Autodesk Fusion 360 part; units mm, degrees
(part 2 of 3)
sketch "Sketch7" plane through (0, 0, 0) normal (-1, 0, 0) x (0, -1, 0)
  line L0 (65.405, -4.7625) -> (65.405, -1.5875)
  line L1 (65.405, -1.5875) -> (133.35, -1.5875)
  line L2 (133.35, -1.5875) -> (133.35, 4.7625)
  line L3 (133.35, 4.7625) -> (-31.75, 4.7625)
  line L4 (-31.75, 4.7625) -> (-31.75, -4.7625)
  line L5 (-31.75, -4.7625) -> (65.405, -4.7625)
  circle A0 centre (117.475, 1.5875) radius 2.1
  dimension "d33" = 4.2
  dimension "d34" = 3.175
  dimension "d35" = 15.875
  measures "d33" diameter of A0
  measures "d34" distance of L3 A0.centre
  measures "d35" distance of L2 A0.centre
extrude "Extrude6" cut sketch "Sketch7" against normal blind 6.35 contours A0
sketch "Sketch8" plane through (0, 0, 0) normal (-1, 0, 0) x (0, -1, 0)
  circle A0 centre (117.475, 1.5875) radius 2.1
  line L0 (65.405, -4.7625) -> (65.405, -1.5875)
  line L1 (65.405, -1.5875) -> (133.35, -1.5875)
  line L2 (133.35, -1.5875) -> (133.35, 4.7625)
  line L3 (133.35, 4.7625) -> (-31.75, 4.7625)
  line L4 (-31.75, 4.7625) -> (-31.75, -4.7625)
  line L5 (-31.75, -4.7625) -> (65.405, -4.7625)
  circle A1 centre (117.475, 11.4427) radius 2.1
  circle A2 centre (117.475, 11.4427) radius 3.175
  circle A3 centre (106.045, 11.4427) radius 2.1
  circle A4 centre (106.045, 11.4427) radius 3.175
  line L6 (117.475, 8.2677) -> (106.045, 8.2677)
  line L7 (117.475, 14.6177) -> (106.045, 14.6177)
  line L8 (106.045, 14.6177) -> (70.9402, 14.6177)
  line L9 (70.9402, 14.6177) -> (65.405, 6.5046)
  line L10 (106.045, 8.2677) -> (74.295, 8.2677)
  line L11 (74.295, 8.2677) -> (65.405, -4.7625)
  line L12 (65.405, 6.5046) -> (65.405, -4.7625)
  line L13 (65.405, 6.5046) -> (64.2164, 4.7625)
  line L14 (120.65, 8.2677) -> (102.87, 8.2677)
  line L15 (102.87, 8.2677) -> (102.87, 14.6177)
  line L16 (102.87, 14.6177) -> (120.65, 14.6177)
  line L17 (120.65, 14.6177) -> (120.65, 8.2677)
  dimension "d38" = 4.2
  dimension "d39" = 9.8552
  dimension "d40" = 6.35
  dimension "d45" = 4.2
  dimension "d46" = 6.35
  dimension "d47" = 11.43
  dimension "d66" = 6.35
  dimension "d68" = 31.75
  dimension "d69" = 6.35
  constraint vertical A0.centre A1.centre
  constraint concentric A1 A2
  constraint concentric A3 A4
  constraint horizontal A1.centre A3.centre
  constraint coincident A2 L6.start
  constraint coincident A4 L6.end
  constraint coincident A2 L7.start
  constraint coincident A4 L7.end
  constraint tangent A4 L7
  constraint horizontal L6
  constraint horizontal L7
  constraint parallel L7 L8
  constraint parallel L3 L10
  constraint coincident L0.start L5.end
  constraint parallel L9 L11
  constraint vertical L9.end L0.start
  constraint coincident L3 L13.end
  constraint parallel L9 L13
  constraint horizontal L14
  constraint vertical L15
  constraint horizontal L16
  constraint vertical L17
  constraint coincident L8 L15.end
  constraint coincident L10 L14.end
  constraint tangent A2 L17
  constraint tangent A4 L15
  measures "d38" diameter of A1
  measures "d39" vertical distance of A0.centre A1.centre
  measures "d40" diameter of A2
  measures "d45" diameter of A3
  measures "d46" diameter of A4
  measures "d47" distance of A1.centre A3.centre
  measures "d66" distance of L8 L10
  measures "d68" distance of L6.end L10.end
  measures "d69" distance of L9 L11
extrude "Extrude7" cut sketch "Sketch8" against normal blind 6.35 contours L0 L1 L11 L12 | L1 L2 L3 L11
extrude "Extrude8" add sketch "Sketch8" along normal blind -6.35 and the other way blind 2.54 contours L0 L1 L11 L12 | L1 L3 L11 L12 | L3 L8 L9 L10 L11 L12 L15 | L3 L12 L13 | A4 L10 L14 L15 | A4 L8 L15 L16 | A4 | A2 A4 L6 L7 L14 L16 | A2 | A2 L14 L17 | A2 L16 L17 | A1 | A3
extrude "Extrude9" add sketch "Sketch8" against normal blind 2.54 contours L0 L1 L11 L12 | A4 L10 L14 L15 | A4 L8 L15 L16 | A4 | A2 A4 L6 L7 L14 L16 | A2 | A2 L14 L17 | A2 L16 L17 | A1 | A3
sketch "Sketch10" plane through (0, 0, -4.7625) normal (0, 0, -1) x (1, 0, 0)
  line L0 (6.35, 65.405) -> (0, 65.405)
  line L1 (0, 65.405) -> (0, -31.75)
  line L2 (0, -31.75) -> (6.35, -31.75)
  line L3 (6.35, -31.75) -> (6.35, 65.405)
  line L4 (6.35, -31.75) -> (0, -31.75)
  line L5 (0, -31.75) -> (0, 65.405)
  line L6 (0, 65.405) -> (6.35, 65.405)
  line L7 (6.35, 65.405) -> (6.35, -31.75)
  constraint horizontal L4
  constraint vertical L5
  constraint horizontal L6
  constraint vertical L7
  constraint coincident L0.end L1.start
  constraint coincident L2.end L3.start
extrude "Extrude12" add sketch "Sketch10" along normal blind 0.4318
sketch "Sketch11" plane through (0, 31.75, 0) normal (0, 1, 0) x (-1, 0, 0)
  line L0 (0, -5.1943) -> (0, 4.7625)
  line L1 (0, 4.7625) -> (-6.35, 4.7625)
  line L2 (-6.35, 4.7625) -> (-6.35, -5.1943)
  line L3 (-6.35, -5.1943) -> (0, -5.1943)
  line L4 (0, -5.1943) -> (-6.35, -5.1943)
  line L5 (-6.35, -5.1943) -> (-6.35, 4.7625)
  line L6 (-6.35, 4.7625) -> (0, 4.7625)
  line L7 (0, 4.7625) -> (0, -5.1943)
  constraint horizontal L4
  constraint vertical L5
  constraint horizontal L6
  constraint vertical L7
  constraint coincident L1.end L2.start
  constraint coincident L0.start L3.end
extrude "Extrude13" add sketch "Sketch11" along normal blind 12.7
sketch "Sketch12" plane through (0, 0, 4.7625) normal (0, 0, 1) x (-1, 0, 0)
  line L0 (-2.54, 64.2164) -> (-6.35, 64.2164)
  line L1 (-6.35, 64.2164) -> (-6.35, -44.45)
  line L2 (-6.35, -44.45) -> (0, -44.45)
  line L3 (0, -44.45) -> (0, 71.9035)
  line L4 (0, 71.9035) -> (-2.54, 71.9035)
  line L5 (-2.54, 71.9035) -> (-2.54, 64.2164)
  line L6 (0, -44.45) -> (-6.35, -44.45)
  line L7 (-6.35, -44.45) -> (-6.35, 6.35)
  line L8 (-6.35, 6.35) -> (0, 6.35)
  line L9 (0, 6.35) -> (0, -44.45)
  dimension "d74" = 50.8
  constraint horizontal L6
  constraint vertical L7
  constraint horizontal L8
  constraint vertical L9
  constraint coincident L1 L7.end
  constraint coincident L2.end L3.start
  measures "d74" distance of L2.end L8.end
extrude "Extrude14" add sketch "Sketch12" along normal blind 6.35 contours L1 L2 L3 L6 L7 L8 L9
sketch "Sketch13" plane through (6.35, 0, 0) normal (1, 0, 0) x (0, 1, 0)
  line L0 (-6.35, 4.7625) -> (-64.2164, 4.7625)
  line L1 (-64.2164, 4.7625) -> (-70.9402, 14.6177)
  line L2 (-70.9402, 14.6177) -> (-120.65, 14.6177)
  line L3 (-120.65, 14.6177) -> (-120.65, 8.2677)
  line L4 (-120.65, 8.2677) -> (-74.295, 8.2677)
  line L5 (-74.295, 8.2677) -> (-65.405, -4.7625)
  line L6 (-65.405, -4.7625) -> (-65.405, -5.1943)
  line L7 (-65.405, -5.1943) -> (44.45, -5.1943)
  line L8 (44.45, -5.1943) -> (44.45, 11.1125)
  line L9 (44.45, 11.1125) -> (-6.35, 11.1125)
  line L10 (-6.35, 11.1125) -> (-6.35, 4.7625)
  line L11 (44.45, -5.1943) -> (-6.35, -5.1943)
  line L12 (-0.4841, 4.9657) -> (-6.35, -5.1943)
  line L13 (44.45, -5.1943) -> (44.45, 4.9657)
  line L14 (-0.4841, 4.9657) -> (44.45, 4.9657)
  dimension "d77" = 10.16
  dimension "d78" = 50.8
  dimension "d79" = 60
  constraint coincident L7.end L8.start
  constraint coincident L7 L11.end
  constraint coincident L8 L13.end
  constraint horizontal L14
  measures "d77" distance of L7.end L13.end
  measures "d78" distance of L7.end L11.end
  measures "d79" angle of L11 L12
extrude "Extrude15" cut sketch "Sketch13" against normal blind 6.35 contours L7 L8 L11 L12 L13 L14
fillet "Fillet1" radius 19.05 1 edges at (3.175, -6.35, 4.7625)
fillet "Fillet2" radius 6.35 1 edges at (3.175, -0.4841, 4.9657)
sketch "Sketch15" plane through (0, 44.45, 0) normal (0, 1, 0) x (-1, 0, 0)
  line L0 (-6.35, 4.9657) -> (0, 4.9657)
  line L1 (0, 4.9657) -> (0, 11.1125)
  line L2 (0, 11.1125) -> (-6.35, 11.1125)
  line L3 (-6.35, 11.1125) -> (-6.35, 4.9657)
  line L4 (34.925, 34) -> (-41.275, 34)
  line L5 (-41.275, 34) -> (-41.275, -42.2)
  line L6 (-41.275, -42.2) -> (34.925, -42.2)
  line L7 (34.925, -42.2) -> (34.925, 34)
  line L8 (34.925, 34) -> (-41.275, -42.2) construction
  line L9 (-41.275, 34) -> (34.925, -42.2) construction
  point P0 (-3.175, -4.1)
  dimension "d92" = 76.2
  dimension "d93" = 76.2
  dimension "d94" = 9.0657
  dimension "d95" = 34.925
  constraint horizontal L4
  constraint perpendicular L4 L5
  constraint parallel L4 L6
  constraint parallel L5 L7
  constraint coincident L8 P0
  constraint coincident L9 P0
  measures "d92" distance of L5.end L6.end
  measures "d93" distance of L4.end L5.end
  measures "d94" distance of L0 P0
  measures "d95" distance of L1 L7
extrude "Extrude19" cut sketch "Sketch15" against normal blind 118.745 contours L0 L1 L2 L3 | L4 L5 L6 L7
extrude "Extrude20" cut 1 faces at (3.81, -74.295, 10.3844) along direction (0, -1, 0) blind 12.7
extrude "Extrude16" [suppressed]
extrude "Extrude17" [suppressed]
sketch "Sketch14" plane through (6.35, 0, 0) normal (1, 0, 0) x (0, 1, 0)
  line L0 (-6.35, -5.1943) -> (-2.3172, 1.7907)
  arc A0 (3.1821, 4.9657) -> (-2.3172, 1.7907) centre (3.1821, -1.3843) ccw
  line L1 (3.1821, 4.9657) -> (44.45, 4.9657)
  line L2 (44.45, 4.9657) -> (44.45, 11.1125)
  line L3 (44.45, 11.1125) -> (-6.35, 11.1125)
  arc A1 (-20.549, 4.7625) -> (-6.35, 11.1125) centre (-20.549, 23.8125) ccw
  line L4 (-20.549, 4.7625) -> (-64.2164, 4.7625)
  line L5 (-64.2164, 4.7625) -> (-70.9402, 14.6177)
  line L6 (-70.9402, 14.6177) -> (-120.65, 14.6177)
  line L7 (-120.65, 14.6177) -> (-120.65, 8.2677)
  line L8 (-120.65, 8.2677) -> (-74.295, 8.2677)
  line L9 (-74.295, 8.2677) -> (-65.405, -4.7625)
  line L10 (-65.405, -4.7625) -> (-65.405, -5.1943)
  line L11 (-65.405, -5.1943) -> (-6.35, -5.1943)
  line L12 (-74.295, 8.2677) -> (-74.295, 14.6177)
  constraint coincident L8.end L9.start
  constraint coincident L6 L12.end
  constraint perpendicular L6 L12
extrude "Extrude18" [suppressed]
sketch "Sketch9" plane through (6.35, 0, 0) normal (1, 0, 0) x (0, 1, 0)
  line L0 (31.75, -5.1943) -> (31.75, 4.7625)
  line L1 (31.75, 4.7625) -> (-64.2164, 4.7625)
  line L2 (17.4625, -1.5875) -> (17.4625, -4.7625)
  line L3 (17.4625, -4.7625) -> (7.9375, -4.7625)
  line L4 (7.9375, -4.7625) -> (7.9375, -1.5875)
  line L5 (7.9375, -1.5875) -> (17.4625, -1.5875)
  line L6 (0, -2.1971) -> (7.9375, -2.1971)
  line L7 (-64.2164, 4.7625) -> (-70.9402, 14.6177)
  line L8 (-70.9402, 14.6177) -> (-120.65, 14.6177)
  line L9 (-120.65, 14.6177) -> (-120.65, 8.2677)
  line L10 (-120.65, 8.2677) -> (-74.295, 8.2677)
  line L11 (-74.295, 8.2677) -> (-65.405, -4.7625)
  line L12 (-65.405, -4.7625) -> (-65.405, -5.1943)
  line L13 (-65.405, -5.1943) -> (31.75, -5.1943)
  dimension "d55" = 9.525
  dimension "d56" = 3.175
  dimension "d57" = 7.9375
  constraint vertical L2
  constraint horizontal L3
  constraint vertical L4
  constraint perpendicular L2 L5
  constraint coincident L4 L6.end
  constraint perpendicular L4 L6
  measures "d55" distance of L4.end L2.start
  measures "d56" distance of L2.end L2.start
  measures "d57" distance of L6.start L6.end
extrude "Extrude10" [suppressed]
extrude "Extrude11" [suppressed]
equation "d7 = 0.5 in - ( 0.2 / 2 ) * 1 in"
equation "d10 = ( 0.375 / 2 ) * 1 in"
equation "d11 = ( ( 1.5 - 1 ) / 2 ) * 1 in"
equation "d39 = 0.263 in + 0.125 in"

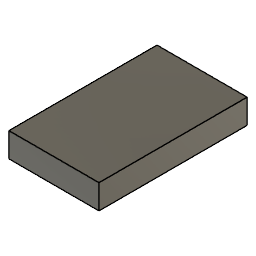
design "Biggest 5 pack ever"
Autodesk Fusion 360 part; units mm, degrees
sketch "Sketch1" plane through (0, 0, 0) normal (0, 0, 1) x (1, 0, 0)
  line L0 (0, 0) -> (58.928, 0)
  line L1 (58.928, 0) -> (58.928, 96.8502)
  line L2 (58.928, 96.8502) -> (0, 96.8502)
  line L3 (0, 96.8502) -> (0, 0)
  dimension "d1" = 96.8502
  dimension "d2" = 58.928
  constraint horizontal L0
  constraint vertical L1
  constraint horizontal L2
  constraint vertical L3
  constraint coincident L0.start L3.end
  measures "d1" distance of L0.start L2.end
  measures "d2" distance of L0.start L0.end
extrude "Extrude1" add sketch "Sketch1" along normal blind 16.002

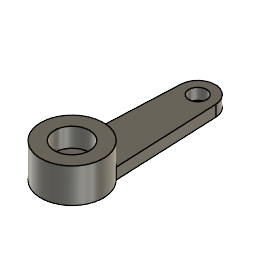
design "MicroServo horn"
Autodesk Fusion 360 part; units mm, degrees
sketch "Sketch1" plane through (0, 0, 0) normal (0, 0, 1) x (1, 0, 0)
  circle A0 centre (0, 0) radius 3.5243
  line L0 (-2.4892, 2.4948) -> (-1.9685, 14.2773)
  line L1 (2.4892, 2.4948) -> (1.9685, 14.2773)
  arc A1 (1.9685, 14.2773) -> (-1.9685, 14.2773) centre (0, 14.1903) ccw
  line L2 (-12.7, 16.1608) -> (12.7, 16.1608)
  line L3 (-12.7, -3.5242) -> (12.7, -3.5243)
  circle A2 centre (0, 14.1903) radius 1
  dimension "d1" = 7.0485
  dimension "d2" = 4.9784
  dimension "d5" = 19.685
  dimension "d7" = 3.937
  dimension "d8" = 2
  dimension "d9" = 25.4
  dimension "d10" = 12.7
  constraint coincident A0.centre origin
  constraint coincident A0 L0.start
  constraint coincident A0 L1.start
  constraint tangent L0 A1
  constraint horizontal L2
  constraint tangent A1 L2
  constraint vertical A0.centre A1.centre
  constraint horizontal L0.end L1.end
  constraint tangent A0 L3
  constraint horizontal L3
  constraint horizontal L0.start L1.start
  constraint concentric A1 A2
  constraint vertical L2.start L3.start
  constraint vertical L2.end L3.end
  measures "d1" diameter of A0
  measures "d2" horizontal distance of L0.start L1.start
  measures "d5" distance of L2 L3
  measures "d7" distance of L0.end L1.end
  measures "d8" diameter of A2
  measures "d9" distance of L2.start L2.end
  measures "d10" horizontal distance of A1.centre L2.start
extrude "Extrude1" add sketch "Sketch1" along normal blind 1.27
extrude "Extrude2" add sketch "Sketch1" along normal blind 3.8735 contours A0
sketch "Sketch2" plane through (0, 0, 3.8735) normal (0, 0, 1) x (-1, 0, 0)
  circle A0 centre (0, 0) radius 3.5242
  circle A1 centre (0, 0) radius 1.9812
  dimension "d15" = 3.9624
  constraint coincident A0.centre A1.centre
  measures "d15" diameter of A1
extrude "Extrude3" cut sketch "Sketch2" against normal blind 2.159 contours A1

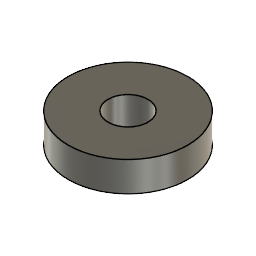
design "Front Wheel"
Autodesk Fusion 360 part; units mm, degrees
sketch "Sketch1" plane through (0, 0, 0) normal (0, 0, 1) x (1, 0, 0)
  circle A0 centre (0, 0) radius 19.05
  circle A1 centre (0, 0) radius 6.35
  dimension "d1" = 12.7
  dimension "d2" = 38.1
  constraint coincident A0.centre A1.centre
  measures "d1" diameter of A1
  measures "d2" diameter of A0
extrude "Extrude1" add sketch "Sketch1" along normal blind 9.525
equation "d3 = ( 3 / 8 ) * 1 in"

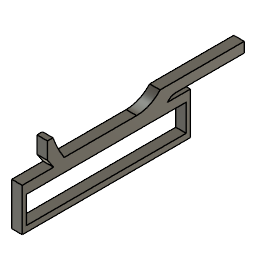
design "Left Cross Base Beam"
Autodesk Fusion 360 part; units mm, degrees
sketch "Sketch1" plane through (0, 0, 0) normal (1, 0, 0) x (0, 1, 0)
  circle A0 centre (0, 0) radius 2.1971
  circle A1 centre (25.4, 0) radius 2.1971
  line L0 (10.16, 2.54) -> (15.24, 2.54)
  line L1 (15.24, 2.54) -> (15.24, -2.54)
  line L2 (15.24, -2.54) -> (10.16, -2.54)
  line L3 (10.16, -2.54) -> (10.16, 2.54)
  line L4 (-6.35, 4.7625) -> (31.75, 4.7625)
  line L5 (31.75, 4.7625) -> (31.75, -4.7625)
  line L6 (31.75, -4.7625) -> (-6.35, -4.7625)
  line L7 (-6.35, -4.7625) -> (-6.35, 4.7625)
  dimension "d1" = 25.4
  dimension "d2" = 4.3942
  dimension "d3" = 4.3942
  dimension "d4" = 5.08
  dimension "d5" = 5.08
  dimension "d6" = 2.54
  dimension "d7" = 10.16
  dimension "d8" = 9.525
  dimension "d9" = 38.1
  dimension "d10" = 4.7625
  dimension "d11" = 6.35
  constraint horizontal A0.centre A1.centre
  constraint horizontal L0
  constraint vertical L1
  constraint horizontal L2
  constraint vertical L3
  constraint coincident A0.centre origin
  constraint horizontal L4
  constraint vertical L5
  constraint horizontal L6
  constraint vertical L7
  measures "d1" distance of A0.centre A1.centre
  measures "d2" diameter of A0
  measures "d3" diameter of A1
  measures "d4" distance of L0.start L0.end
  measures "d5" distance of L0.start L2.end
  measures "d6" distance of A0.centre L0
  measures "d7" horizontal distance of A0.centre L2.end
  measures "d8" distance of L4.start L6.end
  measures "d9" distance of L4.start L4.end
  measures "d10" distance of A0.centre L4
  measures "d11" distance of A0.centre L7
extrude "Extrude1" add sketch "Sketch1" along normal blind 2.54 contours A0 | A1 | L0 L1 L2 L3 | L4 L5 L6 L7
sketch "Sketch2" plane through (2.54, 0, 0) normal (1, 0, 0) x (0, 1, 0)
  line L0 (-6.35, -4.7625) -> (31.75, -4.7625)
  line L1 (31.75, -4.7625) -> (31.75, 4.7625)
  line L2 (31.75, 4.7625) -> (-6.35, 4.7625)
  line L3 (-6.35, 4.7625) -> (-6.35, -4.7625)
  line L4 (31.75, 4.7625) -> (-6.35, 4.7625)
  line L5 (-6.35, 4.7625) -> (-6.35, -4.7625)
  line L6 (-6.35, -4.7625) -> (31.75, -4.7625)
  line L7 (31.75, -4.7625) -> (31.75, 4.7625)
  circle A0 centre (0, 0) radius 2.1971
  circle A1 centre (25.4, 0) radius 2.1971
  dimension "d14" = 4.3942
  dimension "d15" = 4.3942
  constraint horizontal L4
  constraint vertical L5
  constraint horizontal L6
  constraint vertical L7
  constraint coincident L0.start L3.end
  constraint coincident L1.end L2.start
  measures "d14" diameter of A0
  measures "d15" diameter of A1
extrude "Extrude2" add sketch "Sketch2" along normal blind 3.81 contours L0 L1 L2 L3 L4 L5 L6 L7 | A0 | A1
sketch "Sketch3" plane through (0, -6.35, 0) normal (0, -1, 0) x (1, 0, 0)
  line L0 (0, 4.7625) -> (0, -4.7625)
  line L1 (0, -4.7625) -> (6.35, -4.7625)
  line L2 (6.35, -4.7625) -> (6.35, 4.7625)
  line L3 (6.35, 4.7625) -> (0, 4.7625)
  line L4 (0, 4.7625) -> (6.35, 4.7625)
  line L5 (6.35, 4.7625) -> (6.35, -4.7625)
  line L6 (6.35, -4.7625) -> (0, -4.7625)
  line L7 (0, -4.7625) -> (0, 4.7625)
  constraint horizontal L4
  constraint vertical L5
  constraint horizontal L6
  constraint vertical L7
  constraint coincident L1.end L2.start
  constraint coincident L0.start L3.end
extrude "Extrude3" add sketch "Sketch3" along normal blind 127
sketch "Sketch4" plane through (6.35, 0, 0) normal (1, 0, 0) x (0, 1, 0)
  line L0 (31.75, -4.7625) -> (31.75, 4.7625)
  line L1 (31.75, 4.7625) -> (-133.35, 4.7625)
  line L2 (-133.35, 4.7625) -> (-133.35, -4.7625)
  line L3 (-133.35, -4.7625) -> (31.75, -4.7625)
  circle A0 centre (-47.625, 1.5875) radius 1.6
  circle A1 centre (-22.225, 1.5875) radius 1.6
  dimension "d22" = 3.2
  dimension "d23" = 3.2
  dimension "d27" = 6.35
  dimension "d62" = 25.4
  constraint horizontal A0.centre A1.centre
  measures "d22" diameter of A0
  measures "d23" diameter of A1
  measures "d27" distance of L3 A1.centre
  measures "d62" distance of A0.centre A1.centre
sketch "Sketch6" plane through (0, -133.35, 0) normal (0, -1, 0) x (1, 0, 0)
  line L0 (0, -4.7625) -> (6.35, -4.7625)
  line L1 (6.35, -4.7625) -> (6.35, 4.7625)
  line L2 (6.35, 4.7625) -> (0, 4.7625)
  line L3 (0, 4.7625) -> (0, -4.7625)
  line L4 (0, 4.7625) -> (6.35, 4.7625)
  line L5 (6.35, 4.7625) -> (6.35, -1.5875)
  line L6 (6.35, -1.5875) -> (0, -1.5875)
  line L7 (0, -1.5875) -> (0, 4.7625)
  dimension "d29" = 6.35
  dimension "d30" = 6.35
  constraint horizontal L4
  constraint vertical L5
  constraint horizontal L6
  constraint vertical L7
  constraint coincident L2.end L3.start
  measures "d29" distance of L2.end L1.end
  measures "d30" distance of L2.end L6.end
extrude "Extrude5" cut sketch "Sketch6" against normal blind 67.945 contours L0 L1 L3 L6
sketch "Sketch7" plane through (0, 0, 0) normal (-1, 0, 0) x (0, -1, 0)
  line L0 (65.405, -4.7625) -> (65.405, -1.5875)
  line L1 (65.405, -1.5875) -> (133.35, -1.5875)
  line L2 (133.35, -1.5875) -> (133.35, 4.7625)
  line L3 (133.35, 4.7625) -> (-31.75, 4.7625)
  line L4 (-31.75, 4.7625) -> (-31.75, -4.7625)
  line L5 (-31.75, -4.7625) -> (65.405, -4.7625)
  circle A0 centre (117.475, 1.5875) radius 2.1
  dimension "d33" = 4.2
  dimension "d34" = 3.175
  dimension "d35" = 15.875
  measures "d33" diameter of A0
  measures "d34" distance of L3 A0.centre
  measures "d35" distance of L2 A0.centre
extrude "Extrude6" cut sketch "Sketch7" against normal blind 6.35 contours A0
sketch "Sketch8" plane through (0, 0, 0) normal (-1, 0, 0) x (0, -1, 0)
  circle A0 centre (117.475, 1.5875) radius 2.1
  line L0 (65.405, -4.7625) -> (65.405, -1.5875)
  line L1 (65.405, -1.5875) -> (133.35, -1.5875)
  line L2 (133.35, -1.5875) -> (133.35, 4.7625)
  line L3 (133.35, 4.7625) -> (-31.75, 4.7625)
  line L4 (-31.75, 4.7625) -> (-31.75, -4.7625)
  line L5 (-31.75, -4.7625) -> (65.405, -4.7625)
  circle A1 centre (117.475, 11.4427) radius 2.1
  circle A2 centre (117.475, 11.4427) radius 3.175
  circle A3 centre (106.045, 11.4427) radius 2.1
  circle A4 centre (106.045, 11.4427) radius 3.175
  line L6 (117.475, 8.2677) -> (106.045, 8.2677)
  line L7 (117.475, 14.6177) -> (106.045, 14.6177)
  line L8 (106.045, 14.6177) -> (70.9402, 14.6177)
  line L9 (70.9402, 14.6177) -> (65.405, 6.5046)
  line L10 (106.045, 8.2677) -> (74.295, 8.2677)
  line L11 (74.295, 8.2677) -> (65.405, -4.7625)
  line L12 (65.405, 6.5046) -> (65.405, -4.7625)
  line L13 (65.405, 6.5046) -> (64.2164, 4.7625)
  line L14 (120.65, 8.2677) -> (102.87, 8.2677)
  line L15 (102.87, 8.2677) -> (102.87, 14.6177)
  line L16 (102.87, 14.6177) -> (120.65, 14.6177)
  line L17 (120.65, 14.6177) -> (120.65, 8.2677)
  dimension "d38" = 4.2
  dimension "d39" = 9.8552
  dimension "d40" = 6.35
  dimension "d45" = 4.2
  dimension "d46" = 6.35
  dimension "d47" = 11.43
  dimension "d66" = 6.35
  dimension "d68" = 31.75
  dimension "d69" = 6.35
  constraint vertical A0.centre A1.centre
  constraint concentric A1 A2
  constraint concentric A3 A4
  constraint horizontal A1.centre A3.centre
  constraint coincident A2 L6.start
  constraint coincident A4 L6.end
  constraint coincident A2 L7.start
  constraint coincident A4 L7.end
  constraint tangent A4 L7
  constraint horizontal L6
  constraint horizontal L7
  constraint parallel L7 L8
  constraint parallel L3 L10
  constraint coincident L0.start L5.end
  constraint parallel L9 L11
  constraint vertical L9.end L0.start
  constraint coincident L3 L13.end
  constraint parallel L9 L13
  constraint horizontal L14
  constraint vertical L15
  constraint horizontal L16
  constraint vertical L17
  constraint coincident L8 L15.end
  constraint coincident L10 L14.end
  constraint tangent A2 L17
  constraint tangent A4 L15
  measures "d38" diameter of A1
  measures "d39" vertical distance of A0.centre A1.centre
  measures "d40" diameter of A2
  measures "d45" diameter of A3
  measures "d46" diameter of A4
  measures "d47" distance of A1.centre A3.centre
  measures "d66" distance of L8 L10
  measures "d68" distance of L6.end L10.end
  measures "d69" distance of L9 L11
extrude "Extrude7" cut sketch "Sketch8" against normal blind 6.35 contours L0 L1 L11 L12 | L1 L2 L3 L11
extrude "Extrude8" add sketch "Sketch8" along normal blind -6.35 and the other way blind 2.54 contours L0 L1 L11 L12 | L1 L3 L11 L12 | L3 L8 L9 L10 L11 L12 L15 | L3 L12 L13 | A4 L10 L14 L15 | A4 L8 L15 L16 | A4 | A2 A4 L6 L7 L14 L16 | A2 | A2 L14 L17 | A2 L16 L17 | A1 | A3
extrude "Extrude9" add sketch "Sketch8" against normal blind 2.54 contours L0 L1 L11 L12 | A4 L10 L14 L15 | A4 L8 L15 L16 | A4 | A2 A4 L6 L7 L14 L16 | A2 | A2 L14 L17 | A2 L16 L17 | A1 | A3
sketch "Sketch10" plane through (0, 0, -4.7625) normal (0, 0, -1) x (1, 0, 0)
  line L0 (6.35, 65.405) -> (0, 65.405)
  line L1 (0, 65.405) -> (0, -31.75)
  line L2 (0, -31.75) -> (6.35, -31.75)
  line L3 (6.35, -31.75) -> (6.35, 65.405)
  line L4 (6.35, -31.75) -> (0, -31.75)
  line L5 (0, -31.75) -> (0, 65.405)
  line L6 (0, 65.405) -> (6.35, 65.405)
  line L7 (6.35, 65.405) -> (6.35, -31.75)
  constraint horizontal L4
  constraint vertical L5
  constraint horizontal L6
  constraint vertical L7
  constraint coincident L0.end L1.start
  constraint coincident L2.end L3.start
extrude "Extrude12" add sketch "Sketch10" along normal blind 0.4318
sketch "Sketch11" plane through (0, 31.75, 0) normal (0, 1, 0) x (-1, 0, 0)
  line L0 (0, -5.1943) -> (0, 4.7625)
  line L1 (0, 4.7625) -> (-6.35, 4.7625)
  line L2 (-6.35, 4.7625) -> (-6.35, -5.1943)
  line L3 (-6.35, -5.1943) -> (0, -5.1943)
  line L4 (0, -5.1943) -> (-6.35, -5.1943)
  line L5 (-6.35, -5.1943) -> (-6.35, 4.7625)
  line L6 (-6.35, 4.7625) -> (0, 4.7625)
  line L7 (0, 4.7625) -> (0, -5.1943)
  constraint horizontal L4
  constraint vertical L5
  constraint horizontal L6
  constraint vertical L7
  constraint coincident L1.end L2.start
  constraint coincident L0.start L3.end
extrude "Extrude13" add sketch "Sketch11" along normal blind 12.7
sketch "Sketch12" plane through (0, 0, 4.7625) normal (0, 0, 1) x (-1, 0, 0)
  line L0 (-2.54, 64.2164) -> (-6.35, 64.2164)
  line L1 (-6.35, 64.2164) -> (-6.35, -44.45)
  line L2 (-6.35, -44.45) -> (0, -44.45)
  line L3 (0, -44.45) -> (0, 71.9035)
  line L4 (0, 71.9035) -> (-2.54, 71.9035)
  line L5 (-2.54, 71.9035) -> (-2.54, 64.2164)
  line L6 (0, -44.45) -> (-6.35, -44.45)
  line L7 (-6.35, -44.45) -> (-6.35, 6.35)
  line L8 (-6.35, 6.35) -> (0, 6.35)
  line L9 (0, 6.35) -> (0, -44.45)
  dimension "d74" = 50.8
  constraint horizontal L6
  constraint vertical L7
  constraint horizontal L8
  constraint vertical L9
  constraint coincident L1 L7.end
  constraint coincident L2.end L3.start
  measures "d74" distance of L2.end L8.end
extrude "Extrude14" add sketch "Sketch12" along normal blind 6.35 contours L1 L2 L3 L6 L7 L8 L9
sketch "Sketch13" plane through (6.35, 0, 0) normal (1, 0, 0) x (0, 1, 0)
  line L0 (-6.35, 4.7625) -> (-64.2164, 4.7625)
  line L1 (-64.2164, 4.7625) -> (-70.9402, 14.6177)
  line L2 (-70.9402, 14.6177) -> (-120.65, 14.6177)
  line L3 (-120.65, 14.6177) -> (-120.65, 8.2677)
  line L4 (-120.65, 8.2677) -> (-74.295, 8.2677)
  line L5 (-74.295, 8.2677) -> (-65.405, -4.7625)
  line L6 (-65.405, -4.7625) -> (-65.405, -5.1943)
  line L7 (-65.405, -5.1943) -> (44.45, -5.1943)
  line L8 (44.45, -5.1943) -> (44.45, 11.1125)
  line L9 (44.45, 11.1125) -> (-6.35, 11.1125)
  line L10 (-6.35, 11.1125) -> (-6.35, 4.7625)
  line L11 (44.45, -5.1943) -> (-6.35, -5.1943)
  line L12 (-0.4841, 4.9657) -> (-6.35, -5.1943)
  line L13 (44.45, -5.1943) -> (44.45, 4.9657)
  line L14 (-0.4841, 4.9657) -> (44.45, 4.9657)
  dimension "d77" = 10.16
  dimension "d78" = 50.8
  dimension "d79" = 60
  constraint coincident L7.end L8.start
  constraint coincident L7 L11.end
  constraint coincident L8 L13.end
  constraint horizontal L14
  measures "d77" distance of L7.end L13.end
  measures "d78" distance of L7.end L11.end
  measures "d79" angle of L11 L12
extrude "Extrude15" cut sketch "Sketch13" against normal blind 6.35 contours L7 L8 L11 L12 L13 L14
fillet "Fillet1" radius 19.05 1 edges at (3.175, -6.35, 4.7625)
fillet "Fillet2" radius 6.35 1 edges at (3.175, -0.4841, 4.9657)
extrude "Extrude19" cut 1 faces at (2.1167, -120.65, 12.501) along direction (0, 1, 0) blind 46.355
sketch "Sketch15" plane through (0, 0, 0) normal (-1, 0, 0) x (0, -1, 0)
  line L0 (-44.45, 4.9657) -> (-3.1821, 4.9657)
  arc A0 (2.3172, 1.7907) -> (-3.1821, 4.9657) centre (-3.1821, -1.3843) ccw
  line L1 (2.3172, 1.7907) -> (6.35, -5.1943)
  line L2 (6.35, -5.1943) -> (65.405, -5.1943)
  line L3 (65.405, -5.1943) -> (65.405, -4.7625)
  line L4 (65.405, -4.7625) -> (71.9035, 4.7625)
  line L5 (71.9035, 4.7625) -> (20.549, 4.7625)
  arc A1 (6.35, 11.1125) -> (20.549, 4.7625) centre (20.549, 23.8125) ccw
  line L6 (6.35, 11.1125) -> (-44.45, 11.1125)
  line L7 (-44.45, 11.1125) -> (-44.45, 4.9657)
  line L8 (65.405, -4.7625) -> (65.405, 4.7625)
  constraint coincident L3.end L4.start
  constraint coincident L5 L8.end
  constraint perpendicular L5 L8
extrude "Extrude20" cut sketch "Sketch15" against normal blind 2.54 contours L4 L5 L8
extrude "Extrude21" add 1 faces at (4.2333, -45.72, -5.1943) along direction (0, 0, -1) blind 17.78
extrude "Extrude23" add 1 faces at (2.54, -70.2134, 9.216) along direction (-1, 0, 0) blind 2.54
extrude "Extrude25" add 1 faces at (2.1167, -72.0585, 14.6177) along direction (0, 0, 1) blind 3.81
fillet "Fillet3" radius 63.5 1 edges at (3.175, -70.9402, 14.6177)
extrude "Extrude26" add 1 faces at (2.1167, -65.405, -16.9037) along direction (0, -1, 0) blind 24.13
extrude "Extrude27" add 1 faces at (4.2333, -6.35, -17.0476) along direction (0, 1, 0) blind 18.288
extrude "Extrude28" add 1 faces at (2.1167, -81.4917, -4.7625) along direction (0, 0, 1) blind 7.62
extrude "Extrude29" add 1 faces at (4.2333, -0.254, -5.1943) along direction (0, 0, 1) blind 7.62
sketch "Sketch18" plane through (0, 0, 0) normal (-1, 0, 0) x (0, -1, 0)
  line L0 (70.6038, 2.8575) -> (74.295, 8.2677)
  line L1 (74.295, 8.2677) -> (74.295, 18.4277)
  line L2 (64.2164, 4.7625) -> (20.549, 4.7625)
  arc A0 (6.35, 11.1125) -> (20.549, 4.7625) centre (20.549, 23.8125) ccw
  line L3 (6.35, 11.1125) -> (-44.45, 11.1125)
  line L4 (-44.45, 11.1125) -> (-44.45, 4.9657)
  line L5 (-44.45, 4.9657) -> (-3.1821, 4.9657)
  arc A1 (1.8979, 2.4257) -> (-3.1821, 4.9657) centre (-3.1821, -1.3843) ccw
  line L6 (-11.938, -22.9743) -> (89.535, -22.9743)
  line L7 (-9.398, -3.1623) -> (86.995, -3.1623)
  line L8 (86.995, -3.1623) -> (86.995, -19.4183)
  line L9 (86.995, -19.4183) -> (-9.398, -19.4183)
  line L10 (-9.398, -19.4183) -> (-9.398, -3.1623)
  line L11 (74.295, 18.4277) -> (70.9402, 18.4277)
  arc A2 (64.2164, 4.7625) -> (70.9402, 18.4277) centre (11.0131, 39.4274) ccw
  line L12 (-11.938, 2.4257) -> (-11.938, -22.9743)
  line L13 (89.535, -22.9743) -> (89.535, 2.8575)
  line L14 (89.535, 2.8575) -> (70.6038, 2.8575)
  line L15 (1.8979, 2.4257) -> (-11.938, 2.4257)
  dimension "d102" = 16.256
  dimension "d103" = 3.556
  dimension "d120" = 2.54
  dimension "d121" = 2.54
  constraint horizontal L7
  constraint vertical L8
  constraint horizontal L9
  constraint vertical L10
  measures "d102" distance of L7.start L9.end
  measures "d103" distance of L6 L9
  measures "d120" distance of L10 L12
  measures "d121" distance of L8 L13
extrude "Extrude24" cut sketch "Sketch18" against normal blind 6.35 contours L7 L8 L9 L10
sketch "Sketch17" plane through (6.35, 0, 0) normal (1, 0, 0) x (0, 1, 0)
  line L0 (-74.295, 14.6177) -> (-74.295, 8.2677)
  line L1 (-74.295, 8.2677) -> (-65.405, -4.7625)
  line L2 (-65.405, -4.7625) -> (-65.405, -22.9743)
  line L3 (-65.405, -22.9743) -> (-6.35, -22.9743)
  line L4 (-6.35, -22.9743) -> (-6.35, -5.1943)
  line L5 (-6.35, -5.1943) -> (-2.3172, 1.7907)
  arc A0 (3.1821, 4.9657) -> (-2.3172, 1.7907) centre (3.1821, -1.3843) ccw
  line L6 (3.1821, 4.9657) -> (44.45, 4.9657)
  line L7 (44.45, 4.9657) -> (44.45, 11.1125)
  line L8 (44.45, 11.1125) -> (-6.35, 11.1125)
  arc A1 (-20.549, 4.7625) -> (-6.35, 11.1125) centre (-20.549, 23.8125) ccw
  line L9 (-20.549, 4.7625) -> (-64.2164, 4.7625)
  line L10 (-64.2164, 4.7625) -> (-70.9402, 14.6177)
  line L11 (-70.9402, 14.6177) -> (-74.295, 14.6177)
  line L12 (-69.85, 1.7526) -> (-65.405, -22.9743)
  line L13 (-59.055, -17.8943) -> (-59.055, 1.1557)
  line L14 (-59.055, 1.1557) -> (-15.875, 1.1557)
  line L15 (-15.875, 1.1557) -> (-15.875, -17.8943)
  line L16 (-15.875, -17.8943) -> (-59.055, -17.8943)
  constraint midpoint L1 L12.start
  constraint coincident L2.end L3.start
extrude "Extrude22" [rolled back] along distance -3.81 taper angle 0
equation "d7 = 0.5 in - ( 0.2 / 2 ) * 1 in"
equation "d10 = ( 0.375 / 2 ) * 1 in"
equation "d11 = ( ( 1.5 - 1 ) / 2 ) * 1 in"
equation "d39 = 0.263 in + 0.125 in"

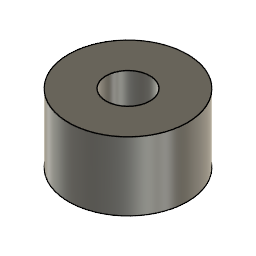
design "Shaft Collar"
Autodesk Fusion 360 part; units mm, degrees
sketch "Sketch1" plane through (0, 0, 0) normal (0, 0, 1) x (1, 0, 0)
  circle A0 centre (0, 0) radius 5.4991
  circle A1 centre (0, 0) radius 2.032
  dimension "d1" = 10.9982
  dimension "d2" = 4.064
  constraint coincident A0.centre A1.centre
  constraint concentric A0 A1
  measures "d1" diameter of A0
  measures "d2" diameter of A1
extrude "Extrude1" add sketch "Sketch1" along normal blind 6.35

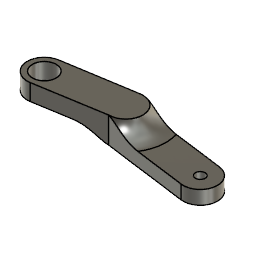
design "Right Control Arm"
Autodesk Fusion 360 part; units mm, degrees
sketch "Sketch1" plane through (0, 0, 0) normal (0, 0, 1) x (1, 0, 0)
  circle A0 centre (0, 0) radius 2.2
  circle A1 centre (28.829, 0) radius 0.9
  circle A2 centre (0, 0) radius 3.175
  circle A3 centre (28.829, 0) radius 3.175
  circle A4 centre (12.954, 2.0955) radius 3.175
  line L0 (28.407994, -3.146963) -> (12.954, -1.0795)
  line L1 (0.517136, -3.132602) -> (12.954, -1.0795)
  line L2 (29.244496, 3.147696) -> (13.369496, 5.243196)
  line L3 (-0.507012, 3.134256) -> (12.446988, 5.229756)
  dimension "d1" = 1.8
  dimension "d2" = 4.4
  dimension "d3" = 28.829
  dimension "d4" = 6.35
  dimension "d5" = 6.35
  dimension "d12" = 6.35
  dimension "d22" = 15.875
  dimension "d23" = 2.0955
  constraint coincident A0.centre A2.centre
  constraint concentric A1 A3
  constraint horizontal A0.centre A1.centre
  constraint coincident A4 L0.end
  constraint tangent A4 L2
  constraint tangent A4 L3
  constraint tangent A3 L2
  constraint tangent A3 L0
  constraint tangent A2 L1
  constraint tangent A2 L3
  constraint vertical A4.centre L0.end
  measures "d1" diameter of A1
  measures "d2" diameter of A0
  measures "d3" distance of A0.centre A1.centre
  measures "d4" diameter of A3
  measures "d5" diameter of A2
  measures "d12" diameter of A4
  measures "d22" horizontal distance of A1.centre A4.centre
  measures "d23" vertical distance of A1.centre A4.centre
extrude "Extrude1" add sketch "Sketch1" along normal blind 2.54 contours A4 | A3 A4 L0 L2 | A3 picked at (13.359471, 1.020697) picked at (22.492534, 0.825939) picked at (28.326881, -2.357846)
extrude "Extrude4" add sketch "Sketch1" along normal blind 5.588 contours A4 picked at (13.359471, 1.020697)
extrude "Extrude3" add sketch "Sketch1" along normal blind 5.588 and the other way blind -1.778 contours A2 | A2 A4 L1 L3 | A4 picked at (-0.65517, 2.767544) picked at (7.597762, 1.223874) picked at (13.359471, 1.020697)
extrude "Extrude5" cut 1 faces at (9.192139, 1.492716, 5.588) along direction (0, 0, -1) blind 0.762
fillet "Fillet1" radius 5.08 1 edges at (16.122167, 1.887304, 2.54)
fillet "Fillet2" radius 5.08 1 edges at (9.789202, 1.841177, 1.778)
sketch "Sketch2" plane through (0, 0, 0) normal (0, 0, -1) x (1, 0, 0)
  circle A0 centre (28.2448, 0) radius 1.5
  line L0 (16.8148, -3.175) -> (28.2448, -3.175)
  arc A1 (28.2448, -3.175) -> (28.2448, 3.175) centre (28.2448, 0) ccw
  line L1 (28.2448, 3.175) -> (16.8148, 3.175)
  circle A2 centre (0, 0) radius 2.0955
  circle A3 centre (0, 0) radius 3.175
  arc A4 (16.8148, 3.175) -> (16.8148, -3.175) centre (16.8148, 0) ccw
  dimension "d8" = 4.191
  dimension "d9" = 6.35
  measures "d8" diameter of A2
  measures "d9" diameter of A3
extrude "Extrude2" [suppressed]
equation "d3 = 1.235 in - 0.1 in"
equation "d23 = ( 0.165 / 2 ) * 1 in"

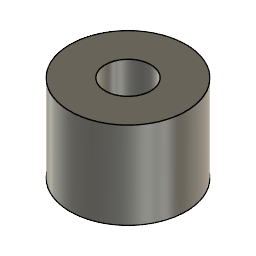
design "Front bushing"
Autodesk Fusion 360 part; units mm, degrees
sketch "Sketch1" plane through (0, 0, 0) normal (0, 0, 1) x (1, 0, 0)
  circle A0 centre (0, 0) radius 6.35
  circle A1 centre (0, 0) radius 2.4956
  dimension "d1" = 12.7
  dimension "d2" = 4.9911
  constraint coincident A0.centre A1.centre
  measures "d1" diameter of A0
  measures "d2" diameter of A1
extrude "Extrude1" add sketch "Sketch1" along normal blind 9.525

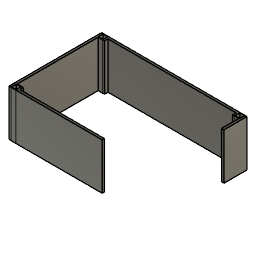
design "Old Dumping Container"
Autodesk Fusion 360 part; units mm, degrees
sketch "Sketch3" plane through (0, 0, 0) normal (0, 0, 1) x (1, 0, 0)
  line L0 (7.1438, 0.7938) -> (2.3813, 0.7938)
  line L1 (2.3813, 0.7938) -> (2.3813, 5.5563)
  line L2 (2.3813, 5.5563) -> (7.1438, 5.5563)
  line L3 (7.1438, 5.5563) -> (7.1438, 0.7938)
  line L4 (7.1438, 96.0438) -> (2.3813, 96.0438)
  line L5 (2.3813, 96.0438) -> (2.3813, 100.8063)
  line L6 (2.3813, 100.8063) -> (7.1438, 100.8063)
  line L7 (7.1438, 100.8063) -> (7.1438, 96.0438)
  line L8 (9.525, 0) -> (0, 0)
  line L9 (0, 0) -> (0, 6.35)
  line L10 (0, 6.35) -> (9.525, 6.35)
  line L11 (9.525, 6.35) -> (9.525, 0)
  line L12 (9.525, 95.25) -> (0, 95.25)
  line L13 (0, 95.25) -> (0, 101.6)
  line L14 (0, 101.6) -> (9.525, 101.6)
  line L15 (9.525, 101.6) -> (9.525, 95.25)
  line L16 (2.1273, 5.8103) -> (7.3977, 5.8103)
  line L17 (7.3977, 5.8103) -> (7.3977, 0.5398)
  line L18 (7.3977, 0.5398) -> (2.1273, 0.5398)
  line L19 (2.1273, 0.5398) -> (2.1273, 5.8103)
  line L20 (7.3977, 101.0603) -> (7.3977, 95.7897)
  line L21 (7.3977, 95.7897) -> (2.1273, 95.7897)
  line L22 (2.1273, 95.7897) -> (2.1273, 101.0603)
  line L23 (2.1273, 101.0603) -> (7.3977, 101.0603)
  line L24 (159.385, 0) -> (149.86, 0)
  line L25 (152.2413, 96.0438) -> (152.2413, 100.8063)
  line L26 (152.2413, 5.5563) -> (157.0038, 5.5563)
  line L27 (159.385, 95.25) -> (149.86, 95.25)
  line L28 (159.385, 6.35) -> (159.385, 0)
  line L29 (157.2578, 5.8103) -> (157.2578, 0.5398)
  line L30 (157.0038, 5.5563) -> (157.0038, 0.7937)
  line L31 (149.86, 0) -> (149.86, 6.35)
  line L32 (157.0038, 96.0438) -> (152.2413, 96.0438)
  line L33 (152.2413, 100.8063) -> (157.0038, 100.8063)
  line L34 (157.2578, 101.0603) -> (157.2578, 95.7898)
  line L35 (151.9873, 101.0603) -> (157.2578, 101.0603)
  line L36 (159.385, 101.6) -> (159.385, 95.25)
  line L37 (157.0038, 0.7937) -> (152.2413, 0.7938)
  line L38 (157.2578, 95.7898) -> (151.9873, 95.7898)
  line L39 (157.0038, 100.8063) -> (157.0038, 96.0438)
  line L40 (149.86, 101.6) -> (159.385, 101.6)
  line L41 (157.2578, 0.5397) -> (151.9873, 0.5397)
  line L42 (149.86, 6.35) -> (159.385, 6.35)
  line L43 (151.9873, 5.8103) -> (157.2578, 5.8103)
  line L44 (149.86, 95.25) -> (149.86, 101.6)
  line L45 (151.9873, 95.7898) -> (151.9873, 101.0602)
  line L46 (152.2413, 0.7938) -> (152.2413, 5.5563)
  line L47 (151.9873, 0.5397) -> (151.9873, 5.8103)
  line L48 (149.86, 101.6) -> (9.525, 101.6)
  line L49 (9.525, 101.6) -> (9.525, 99.06)
  line L50 (9.525, 99.06) -> (149.86, 99.06)
  line L51 (149.86, 99.06) -> (149.86, 101.6)
  line L52 (159.385, 95.25) -> (156.845, 95.25)
  line L53 (156.845, 95.25) -> (156.845, 6.35)
  line L54 (156.845, 6.35) -> (159.385, 6.35)
  line L55 (159.385, 6.35) -> (159.385, 95.25)
  line L56 (149.86, 0) -> (9.525, 0)
  line L57 (9.525, 0) -> (9.525, 2.54)
  line L58 (9.525, 2.54) -> (149.86, 2.54)
  line L59 (149.86, 2.54) -> (149.86, 0)
  line L60 (0, 95.25) -> (2.54, 95.25)
  line L61 (2.54, 95.25) -> (2.54, 6.35)
  line L62 (2.54, 6.35) -> (0, 6.35)
  line L63 (0, 6.35) -> (0, 95.25)
  point P0 (149.86, 0)
  dimension "d31" = 4.7625
  dimension "d37" = 6.35
  dimension "d38" = 9.525
  dimension "d39" = 0.7937
  dimension "d40" = 2.3813
  dimension "d41" = 0.7937
  dimension "d42" = 6.35
  dimension "d43" = 2.3813
  dimension "d52" = 9.525
  dimension "d55" = -0.254
  dimension "d56" = -0.254
  dimension "d66" = 101.6
  dimension "d67" = -0.254
  dimension "d68" = -0.254
  dimension "d69" = 4.7625
  dimension "d70" = 6.35
  dimension "d71" = 9.525
  dimension "d72" = 0.7937
  dimension "d73" = 2.3813
  dimension "d74" = 0.7937
  dimension "d75" = 6.35
  dimension "d76" = 2.3813
  dimension "d77" = 9.525
  dimension "d78" = 101.6
  dimension "d79" = 145.0975
  dimension "d98" = 2.54
  dimension "d99" = 2.54
  dimension "d100" = 2.54
  dimension "d101" = 2.54
  constraint horizontal L0
  constraint vertical L1
  constraint horizontal L2
  constraint vertical L3
  constraint horizontal L4
  constraint vertical L5
  constraint horizontal L6
  constraint vertical L7
  constraint equal L4 L5
  constraint equal L1 L4
  constraint equal L0 L1
  constraint vertical L1.end L4.end
  constraint horizontal L8
  constraint vertical L9
  constraint horizontal L10
  constraint vertical L11
  constraint horizontal L12
  constraint vertical L13
  constraint horizontal L14
  constraint vertical L15
  constraint coincident L8.end L9.start
  constraint horizontal L37
  constraint vertical L46
  constraint horizontal L26
  constraint vertical L30
  constraint horizontal L32
  constraint vertical L25
  constraint horizontal L33
  constraint vertical L39
  constraint equal L25 L32
  constraint equal L32 L46
  constraint equal L37 L46
  constraint vertical L25.start L26.start
  constraint horizontal L24
  constraint vertical L31
  constraint horizontal L42
  constraint vertical L28
  constraint horizontal L27
  constraint vertical L44
  constraint horizontal L40
  constraint vertical L36
  constraint coincident P0 L24.end
  constraint horizontal L8.start P0
  constraint horizontal L48
  constraint vertical L49
  constraint horizontal L50
  constraint vertical L51
  constraint coincident L15 L49.end
  constraint horizontal L52
  constraint vertical L53
  constraint horizontal L54
  constraint vertical L55
  constraint coincident L42 L53.end
  constraint horizontal L56
  constraint vertical L57
  constraint horizontal L58
  constraint vertical L59
  constraint coincident L11 L57.end
  constraint horizontal L60
  constraint vertical L61
  constraint horizontal L62
  constraint vertical L63
  constraint coincident L10 L61.end
  measures "d31" distance of L4.end L5.end
  measures "d37" distance of L8.start L10.end
  measures "d38" distance of L8.start L8.end
  measures "d39" distance of L0 L8
  measures "d40" distance of L3 L11
  measures "d41" distance of L4 L12
  measures "d42" distance of L12.start L14.end
  measures "d43" distance of L7 L15
  measures "d52" distance of L13.end L14.end
  measures "d66" distance of L8 L14
  measures "d69" distance of L25.start L25.end
  measures "d70" distance of L28.start L24.start
  measures "d71" distance of P0 L24.start
  measures "d72" distance of L24 L37
  measures "d73" distance of L28 L30
  measures "d74" distance of L27 L32
  measures "d75" distance of L36.start L27.start
  measures "d76" distance of L36 L39
  measures "d77" distance of L36.start L40.start
  measures "d78" distance of L24 L40
  measures "d79" distance of L7 L25
  measures "d98" distance of L48 L50
  measures "d99" distance of L53 L55
  measures "d100" distance of L56 L58
  measures "d101" distance of L61 L63
extrude "Extrude4" add sketch "Sketch3" along normal blind 50.8 contours L8 L9 L10 L11 L57 L62 | L11 L31 L56 L57 L58 L59 | L24 L28 L31 L42 L54 L59 | L10 L12 L60 L61 L62 L63 | L12 L13 L14 L15 L49 L60 | L27 L42 L52 L53 L54 L55 | L27 L36 L40 L44 L51 L52 | L15 L44 L48 L49 L50 L51
sketch "Sketch6" plane through (159.385, 0, 0) normal (-1, 0, 0) x (0, -1, 0)
  line L0 (-101.6, 0) -> (0, 0)
  line L1 (0, 0) -> (0, 50.8)
  line L2 (0, 50.8) -> (-101.6, 50.8)
  line L3 (-101.6, 50.8) -> (-101.6, 0)
  line L4 (-101.6, 50.8) -> (-76.2, 50.8)
  line L5 (-76.2, 50.8) -> (-76.2, 0)
  line L6 (-76.2, 0) -> (-101.6, 0)
  line L7 (-101.6, 0) -> (-101.6, 50.8)
  line L8 (0, 0) -> (-101.6, 0)
  line L9 (-101.6, 0) -> (-101.6, 50.8)
  line L10 (-101.6, 50.8) -> (0, 50.8)
  line L11 (0, 50.8) -> (0, 0)
  dimension "d102" = 76.2
  constraint horizontal L4
  constraint vertical L5
  constraint horizontal L6
  constraint vertical L7
  constraint coincident L0 L5.end
  constraint coincident L2.end L3.start
  measures "d102" distance of L1 L5
extrude "Extrude10" cut sketch "Sketch6" along normal blind 57.15 contours L0 L1 L2 L5 L8 L10 L11
equation "d39 = ( 1 / 32 ) * 1 in"
equation "d40 = ( 3 / 32 ) * 1 in"
equation "d41 = ( 1 / 32 ) * 1 in"
equation "d43 = ( 3 / 32 ) * 1 in"
equation "d52 = ( 3 / 8 ) * 1 in"
equation "d72 = ( 1 / 32 ) * 1 in"
equation "d73 = ( 3 / 32 ) * 1 in"
equation "d74 = ( 1 / 32 ) * 1 in"
equation "d76 = ( 3 / 32 ) * 1 in"
equation "d77 = ( 3 / 8 ) * 1 in"
equation "d79 = 4.9875 in + 0.725 in"

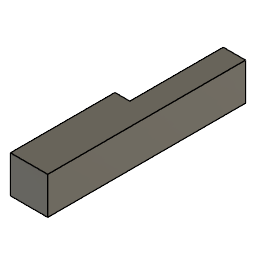
design "Right Fake Cross Beam"
Autodesk Fusion 360 part; units mm, degrees
sketch "Sketch1" plane through (0, 0, 0) normal (1, 0, 0) x (0, 1, 0)
  circle A0 centre (0, 0) radius 2.1971
  circle A1 centre (25.4, 0) radius 2.1971
  line L0 (10.16, 2.54) -> (15.24, 2.54)
  line L1 (15.24, 2.54) -> (15.24, -2.54)
  line L2 (15.24, -2.54) -> (10.16, -2.54)
  line L3 (10.16, -2.54) -> (10.16, 2.54)
  line L4 (-6.35, 4.7625) -> (31.75, 4.7625)
  line L5 (31.75, 4.7625) -> (31.75, -4.7625)
  line L6 (31.75, -4.7625) -> (-6.35, -4.7625)
  line L7 (-6.35, -4.7625) -> (-6.35, 4.7625)
  dimension "d1" = 25.4
  dimension "d2" = 4.3942
  dimension "d3" = 4.3942
  dimension "d4" = 5.08
  dimension "d5" = 5.08
  dimension "d6" = 2.54
  dimension "d7" = 10.16
  dimension "d8" = 9.525
  dimension "d9" = 38.1
  dimension "d10" = 4.7625
  dimension "d11" = 6.35
  constraint horizontal A0.centre A1.centre
  constraint horizontal L0
  constraint vertical L1
  constraint horizontal L2
  constraint vertical L3
  constraint coincident A0.centre origin
  constraint horizontal L4
  constraint vertical L5
  constraint horizontal L6
  constraint vertical L7
  measures "d1" distance of A0.centre A1.centre
  measures "d2" diameter of A0
  measures "d3" diameter of A1
  measures "d4" distance of L0.start L0.end
  measures "d5" distance of L0.start L2.end
  measures "d6" distance of A0.centre L0
  measures "d7" horizontal distance of A0.centre L2.end
  measures "d8" distance of L4.start L6.end
  measures "d9" distance of L4.start L4.end
  measures "d10" distance of A0.centre L4
  measures "d11" distance of A0.centre L7
extrude "Extrude1" add sketch "Sketch1" along normal blind 2.54 contours A0 | A1 | L0 L1 L2 L3 | L4 L5 L6 L7 makes body 1
sketch "Sketch2" plane through (2.54, 0, 0) normal (1, 0, 0) x (0, 1, 0)
  line L0 (-6.35, -4.7625) -> (31.75, -4.7625)
  line L1 (31.75, -4.7625) -> (31.75, 4.7625)
  line L2 (31.75, 4.7625) -> (-6.35, 4.7625)
  line L3 (-6.35, 4.7625) -> (-6.35, -4.7625)
  line L4 (31.75, 4.7625) -> (-6.35, 4.7625)
  line L5 (-6.35, 4.7625) -> (-6.35, -4.7625)
  line L6 (-6.35, -4.7625) -> (31.75, -4.7625)
  line L7 (31.75, -4.7625) -> (31.75, 4.7625)
  circle A0 centre (0, 0) radius 2.1971
  circle A1 centre (25.4, 0) radius 2.1971
  dimension "d14" = 4.3942
  dimension "d15" = 4.3942
  constraint horizontal L4
  constraint vertical L5
  constraint horizontal L6
  constraint vertical L7
  constraint coincident L0.start L3.end
  constraint coincident L1.end L2.start
  measures "d14" diameter of A0
  measures "d15" diameter of A1
extrude "Extrude2" add sketch "Sketch2" along normal blind 3.81 contours L0 L1 L2 L3 L4 L5 L6 L7 | A0 | A1 bodies 1
sketch "Sketch3" plane through (0, -6.35, 0) normal (0, -1, 0) x (1, 0, 0)
  line L0 (0, 4.7625) -> (0, -4.7625)
  line L1 (0, -4.7625) -> (6.35, -4.7625)
  line L2 (6.35, -4.7625) -> (6.35, 4.7625)
  line L3 (6.35, 4.7625) -> (0, 4.7625)
  line L4 (0, 4.7625) -> (6.35, 4.7625)
  line L5 (6.35, 4.7625) -> (6.35, -4.7625)
  line L6 (6.35, -4.7625) -> (0, -4.7625)
  line L7 (0, -4.7625) -> (0, 4.7625)
  constraint horizontal L4
  constraint vertical L5
  constraint horizontal L6
  constraint vertical L7
  constraint coincident L1.end L2.start
  constraint coincident L0.start L3.end
extrude "Extrude3" add sketch "Sketch3" along normal blind 127 bodies 1
sketch "Sketch4" plane through (6.35, 0, 0) normal (1, 0, 0) x (0, 1, 0)
  line L0 (31.75, -4.7625) -> (31.75, 4.7625)
  line L1 (31.75, 4.7625) -> (-133.35, 4.7625)
  line L2 (-133.35, 4.7625) -> (-133.35, -4.7625)
  line L3 (-133.35, -4.7625) -> (31.75, -4.7625)
  circle A0 centre (-22.225, -1.5875) radius 1.6
  circle A1 centre (-47.625, -1.5875) radius 1.6
  dimension "d20" = 3.2
  dimension "d21" = 3.2
  dimension "d24" = 6.35
  dimension "d25" = 22.225
  dimension "d48" = 25.4
  constraint horizontal A0.centre A1.centre
  measures "d20" diameter of A0
  measures "d21" diameter of A1
  measures "d24" distance of L1 A0.centre
  measures "d25" horizontal distance of origin A0.centre
  measures "d48" distance of A0.centre A1.centre
sketch "Sketch5" plane through (0, -133.35, 0) normal (0, -1, 0) x (1, 0, 0)
  line L0 (0, -4.7625) -> (6.35, -4.7625)
  line L1 (6.35, -4.7625) -> (6.35, 4.7625)
  line L2 (6.35, 4.7625) -> (0, 4.7625)
  line L3 (0, 4.7625) -> (0, -4.7625)
  line L4 (0, -4.7625) -> (6.35, -4.7625)
  line L5 (6.35, -4.7625) -> (6.35, 1.5875)
  line L6 (6.35, 1.5875) -> (0, 1.5875)
  line L7 (0, 1.5875) -> (0, -4.7625)
  dimension "d29" = 6.35
  constraint horizontal L4
  constraint vertical L5
  constraint horizontal L6
  constraint vertical L7
  constraint coincident L1 L5.end
  constraint coincident L0.start L3.end
  measures "d29" distance of L0.end L5.end
extrude "Extrude5" cut sketch "Sketch5" against normal blind 67.945 contours L1 L2 L3 L6 bodies 1
sketch "Sketch6" plane through (0, 0, 0) normal (-1, 0, 0) x (0, -1, 0)
  line L0 (65.405, 1.5875) -> (65.405, 4.7625)
  line L1 (65.405, 4.7625) -> (-31.75, 4.7625)
  line L2 (-31.75, 4.7625) -> (-31.75, -4.7625)
  line L3 (-31.75, -4.7625) -> (133.35, -4.7625)
  line L4 (133.35, -4.7625) -> (133.35, 1.5875)
  line L5 (133.35, 1.5875) -> (65.405, 1.5875)
  circle A0 centre (117.475, -1.5875) radius 2.1
  dimension "d32" = 4.2
  dimension "d33" = 15.875
  dimension "d34" = 3.175
  measures "d32" diameter of A0
  measures "d33" distance of L4 A0.centre
  measures "d34" distance of L3 A0.centre
extrude "Extrude6" cut sketch "Sketch6" against normal blind 6.35 contours A0 bodies 1